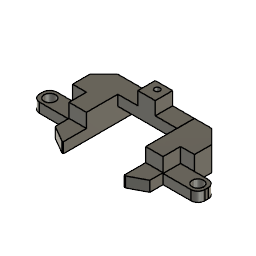
Frame (Autodesk Fusion 360 archive; units mm, degrees)
design "Static Arm"
Autodesk Fusion 360 part; units mm, degrees
(part 1 of 2)
sketch "Sketch1" plane through (0, 0, 0) normal (0, 0, 1) x (1, 0, 0)
  line L0 (2.54, 0) -> (57.7596, 0)
  line L1 (60.2996, 2.54) -> (60.2996, 3.81)
  line L2 (57.7596, 6.35) -> (2.54, 6.35)
  line L3 (0, 3.81) -> (0, 2.54)
  circle A0 centre (3.175, 3.175) radius 2.0955
  circle A1 centre (57.1246, 3.175) radius 2.0955
  arc A2 (60.2996, 3.81) -> (57.7596, 6.35) centre (57.7596, 3.81) ccw
  arc A3 (57.7596, 0) -> (60.2996, 2.54) centre (57.7596, 2.54) ccw
  arc A4 (2.54, 6.35) -> (0, 3.81) centre (2.54, 3.81) ccw
  arc A5 (0, 2.54) -> (2.54, 0) centre (2.54, 2.54) ccw
  line L4 (13.335, 17.78) -> (41.275, 17.78)
  line L5 (41.275, 17.78) -> (41.275, 11.43)
  line L6 (41.275, 11.43) -> (13.335, 11.43)
  line L7 (13.335, 11.43) -> (13.335, 17.78)
  line L8 (13.335, 17.78) -> (19.685, 17.78)
  line L9 (19.685, 17.78) -> (19.685, 0)
  line L10 (19.685, 0) -> (13.335, 0)
  line L11 (13.335, 0) -> (13.335, 17.78)
  line L12 (47.5996, 17.78) -> (41.2496, 17.78)
  line L13 (41.2496, 17.78) -> (41.2496, 0)
  line L14 (41.2496, 0) -> (47.5996, 0)
  line L15 (47.5996, 0) -> (47.5996, 17.78)
  line L16 (13.335, 17.78) -> (8.255, 17.78)
  line L17 (8.255, 17.78) -> (8.255, 0)
  line L18 (8.255, 0) -> (13.335, 0)
  line L19 (13.335, 0) -> (13.335, 17.78)
  line L20 (13.335, 17.78) -> (8.255, 12.7)
  line L21 (47.5996, 17.78) -> (52.6796, 17.78)
  line L22 (52.6796, 17.78) -> (52.6796, 0)
  line L23 (52.6796, 0) -> (47.5996, 0)
  line L24 (47.5996, 0) -> (47.5996, 17.78)
  line L25 (47.5996, 17.78) -> (52.6796, 12.7)
  point P0 (60.2996, 0)
  dimension "d1" = 6.35
  dimension "d2" = 60.2996
  dimension "d3" = 4.191
  dimension "d4" = 4.191
  dimension "d5" = 53.9496
  dimension "d6" = 3.175
  dimension "d7" = 3.175
  dimension "d8" = 2.54
  dimension "d9" = 2.54
  dimension "d10" = 2.54
  dimension "d11" = 2.54
  dimension "d14" = 6.35
  dimension "d15" = 10.16
  dimension "d17" = 6.35
  dimension "d18" = 10.16
  dimension "d19" = 5.08
  dimension "d20" = 6.35
  dimension "d39" = 27.94
  dimension "d80" = 5.08
  dimension "d81" = 45
  dimension "d82" = 5.08
  dimension "d83" = 45
  constraint horizontal L0
  constraint vertical L1
  constraint horizontal L2
  constraint vertical L3
  constraint horizontal A0.centre A1.centre
  constraint tangent L2 A2
  constraint tangent L1 A2
  constraint coincident P0 L0
  constraint coincident P0 L1
  constraint tangent L0 A3
  constraint tangent L1 A3
  constraint tangent L3 A4
  constraint tangent L2 A4
  constraint coincident origin L3
  constraint coincident origin L0
  constraint tangent L3 A5
  constraint tangent L0 A5
  constraint horizontal L4
  constraint vertical L5
  constraint horizontal L6
  constraint vertical L7
  constraint horizontal L8
  constraint vertical L9
  constraint horizontal L10
  constraint vertical L11
  constraint coincident L0 L9.end
  constraint horizontal L12
  constraint vertical L13
  constraint horizontal L14
  constraint vertical L15
  constraint coincident L0 L13.end
  constraint coincident L4 L12.start
  constraint horizontal L16
  constraint vertical L17
  constraint horizontal L18
  constraint vertical L19
  constraint coincident L0 L17.end
  constraint coincident L17 L20.end
  constraint horizontal L21
  constraint vertical L22
  constraint horizontal L23
  constraint vertical L24
  constraint coincident L0 L22.end
  constraint coincident L22 L25.end
  measures "d1" distance of L0 L2
  measures "d2" distance of origin P0
  measures "d3" diameter of A0
  measures "d4" diameter of A1
  measures "d5" distance of A0.centre A1.centre
  measures "d6" distance of L3 A0.centre
  measures "d7" vertical distance of origin A0.centre
  measures "d8" radius of A2
  measures "d9" radius of A3
  measures "d10" radius of A4
  measures "d11" radius of A5
  measures "d14" distance of L4 L6
  measures "d15" distance of A0.centre L11
  measures "d17" distance of L13 L15
  measures "d18" distance of A3.centre L15
  measures "d19" distance of L2 L6
  measures "d20" distance of L9 L11
  measures "d39" distance of L4.start L4.end
  measures "d80" distance of L4.start L16.end
  measures "d81" angle of L16 L20
  measures "d82" distance of L12.start L21.end
  measures "d83" angle of L21 L25
extrude "Extrude1" add sketch "Sketch1" along normal blind 3.81 contours L0 L2 L3 A4 A5 L17 | L0 L2 L11 L17 L18 L19 | L0 L2 L9 L10 L11 L19 | L2 L7 L11 L17 L19 L20 | L2 L6 L9 L11 L19 | L0 L2 L13 L14 L15 L24 | L4 L6 L7 L8 L9 L11 L19 | L0 L2 L15 L22 L23 L24 | L2 L5 L6 L12 L13 L15 L24 | L4 L6 L9 L13 | L0 L1 L2 A2 A3 L22 | L2 L15 L22 L24 L25 makes body 1
sketch "Sketch5" plane through (0, 0, 3.81) normal (0, 0, -1) x (1, 0, 0)
  circle A0 centre (63.4746, -3.175) radius 2.0955
  circle A1 centre (3.175, -3.175) radius 2.0955
  line L0 (47.5996, 0) -> (47.5996, -11.43)
  line L1 (47.5996, -11.43) -> (19.335, -11.43)
  line L2 (19.335, -11.43) -> (19.335, 0)
  line L3 (19.335, 0) -> (2.54, 0)
  arc A2 (2.54, 0) -> (0, -2.54) centre (2.54, -2.54) ccw
  line L4 (0, -2.54) -> (0, -3.81)
  arc A3 (0, -3.81) -> (2.54, -6.35) centre (2.54, -3.81) ccw
  line L5 (2.54, -6.35) -> (13.335, -6.35)
  line L6 (13.335, -6.35) -> (13.335, -17.78)
  line L7 (13.335, -17.78) -> (53.9496, -17.78)
  line L8 (53.9496, -17.78) -> (53.9496, -6.35)
  line L9 (53.9496, -6.35) -> (64.1096, -6.35)
  arc A4 (64.1096, -6.35) -> (66.6496, -3.81) centre (64.1096, -3.81) ccw
  line L10 (66.6496, -3.81) -> (66.6496, -2.54)
  arc A5 (66.6496, -2.54) -> (64.1096, 0) centre (64.1096, -2.54) ccw
  line L11 (64.1096, 0) -> (47.5996, 0)
  line L12 (26.9748, -11.43) -> (33.3248, -11.43)
  line L13 (33.3248, -11.43) -> (33.3248, -17.78)
  line L14 (33.3248, -17.78) -> (26.9748, -17.78)
  line L15 (26.9748, -17.78) -> (26.9748, -11.43)
  circle A6 centre (3.175, -3.175) radius 2.0955
  line L16 (8.255, -6.35) -> (2.54, -6.35)
  arc A7 (0, -3.81) -> (2.54, -6.35) centre (2.54, -3.81) ccw
  line L17 (0, -3.81) -> (0, -2.54)
  arc A8 (2.54, 0) -> (0, -2.54) centre (2.54, -2.54) ccw
  line L18 (2.54, 0) -> (19.685, 0)
  line L19 (19.685, 0) -> (19.685, -11.43)
  line L20 (19.685, -11.43) -> (41.2496, -11.43)
  line L21 (41.2496, -11.43) -> (41.2496, -17.78)
  line L22 (41.2496, -17.78) -> (13.335, -17.78)
  line L23 (13.335, -17.78) -> (8.255, -12.7)
  line L24 (8.255, -12.7) -> (8.255, -6.35)
  dimension "d35" = 6.35
  dimension "d36" = 26.9748
  constraint horizontal L12
  constraint vertical L13
  constraint horizontal L14
  constraint vertical L15
  constraint coincident L7 L13.end
  constraint coincident L1 L12.start
  measures "d35" distance of L13 L15
  measures "d36" distance of origin L15
extrude "Extrude4" add sketch "Sketch5" against normal blind 4.8006 contours L1 L7 L12 L13 L14 L15 L20 L22 bodies 1
sketch "Sketch2" plane through (0, 0, 8.6106) normal (0, 0, -1) x (1, 0, 0)
  circle A0 centre (63.4746, -3.175) radius 2.0955
  circle A1 centre (3.175, -3.175) radius 2.0955
  line L0 (47.5996, 0) -> (47.5996, -11.43)
  line L1 (47.5996, -11.43) -> (36.4998, -11.43)
  line L2 (19.335, -11.43) -> (19.335, 0)
  line L3 (19.335, 0) -> (2.54, 0)
  arc A2 (2.54, 0) -> (0, -2.54) centre (2.54, -2.54) ccw
  line L4 (0, -2.54) -> (0, -3.81)
  arc A3 (0, -3.81) -> (2.54, -6.35) centre (2.54, -3.81) ccw
  line L5 (2.54, -6.35) -> (13.335, -6.35)
  line L6 (13.335, -6.35) -> (13.335, -17.78)
  line L7 (36.4998, -17.78) -> (53.9496, -17.78)
  line L8 (53.9496, -17.78) -> (53.9496, -6.35)
  line L9 (53.9496, -6.35) -> (64.1096, -6.35)
  arc A4 (64.1096, -6.35) -> (66.6496, -3.81) centre (64.1096, -3.81) ccw
  line L10 (66.6496, -3.81) -> (66.6496, -2.54)
  arc A5 (66.6496, -2.54) -> (64.1096, 0) centre (64.1096, -2.54) ccw
  line L11 (64.1096, 0) -> (47.5996, 0)
  circle A6 centre (30.1498, -15.3416) radius 1
  line L12 (36.4998, -11.43) -> (36.4998, -17.78)
  line L13 (30.1498, -17.78) -> (30.1498, -11.43)
  line L14 (30.1498, -11.43) -> (19.335, -11.43)
  line L15 (13.335, -17.78) -> (30.1498, -17.78)
  line L16 (30.1498, -17.78) -> (36.4998, -17.78)
  line L17 (36.4998, -17.78) -> (36.4998, -11.43)
  line L18 (36.4998, -11.43) -> (30.1498, -11.43)
  line L19 (30.1498, -11.43) -> (30.1498, -17.78)
  circle A7 centre (63.4746, -3.175) radius 2.0955
  circle A8 centre (3.175, -3.175) radius 2.0955
  line L20 (47.5996, -11.43) -> (47.5996, 0)
  line L21 (2.54, 0) -> (19.335, 0)
  arc A9 (66.6496, -2.54) -> (64.1096, 0) centre (64.1096, -2.54) ccw
  line L22 (66.6496, -2.54) -> (66.6496, -3.81)
  arc A10 (64.1096, -6.35) -> (66.6496, -3.81) centre (64.1096, -3.81) ccw
  line L23 (13.335, -6.35) -> (2.54, -6.35)
  line L24 (53.9496, -6.35) -> (53.9496, -17.78)
  line L25 (30.1498, -17.78) -> (13.335, -17.78)
  line L26 (13.335, -17.78) -> (13.335, -6.35)
  arc A11 (0, -3.81) -> (2.54, -6.35) centre (2.54, -3.81) ccw
  line L27 (0, -3.81) -> (0, -2.54)
  arc A12 (2.54, 0) -> (0, -2.54) centre (2.54, -2.54) ccw
  line L28 (19.335, 0) -> (19.335, -11.43)
  line L29 (19.335, -11.43) -> (30.1498, -11.43)
  line L30 (30.1498, -11.43) -> (30.1498, -17.78)
  line L31 (36.4998, -17.78) -> (36.4998, -11.43)
  line L32 (36.4998, -11.43) -> (47.5996, -11.43)
  line L33 (47.5996, 0) -> (64.1096, 0)
  line L34 (64.1096, -6.35) -> (53.9496, -6.35)
  line L35 (53.9496, -17.78) -> (36.4998, -17.78)
  line L36 (33.3248, -17.78) -> (26.9748, -17.78)
  line L37 (26.9748, -17.78) -> (26.9748, -11.43)
  line L38 (26.9748, -11.43) -> (33.3248, -11.43)
  line L39 (33.3248, -11.43) -> (33.3248, -17.78)
  dimension "d21" = 2
  dimension "d24" = 3.9116
  dimension "d53" = 30.1498
  measures "d21" diameter of A6
  measures "d24" distance of L1 A6.centre
  measures "d53" distance of L4 A6.centre
extrude "Extrude2" cut sketch "Sketch2" along normal blind 12.7 contours A6 L13 L19 L30 | A6 L13 L19 L30 bodies 1
sketch "Sketch3" plane through (0, 0, 3.81) normal (0, 0, 1) x (-1, 0, 0)
  line L0 (-41.2496, 0) -> (-57.7596, 0)
  line L1 (-57.7596, -6.35) -> (-52.6796, -6.35)
  line L2 (-41.275, -11.43) -> (-41.2496, -11.43)
  circle A0 centre (-16.51, -14.605) radius 2.1
  circle A1 centre (-44.4246, -14.605) radius 2.1
  line L3 (-47.5996, -17.78) -> (-41.275, -17.78)
  line L4 (-41.275, -17.78) -> (-41.275, -11.43)
  line L5 (-41.2496, -11.43) -> (-41.2496, 0)
  arc A2 (-57.7596, 0) -> (-60.2996, -2.54) centre (-57.7596, -2.54) ccw
  line L6 (-60.2996, -2.54) -> (-60.2996, -3.81)
  arc A3 (-60.2996, -3.81) -> (-57.7596, -6.35) centre (-57.7596, -3.81) ccw
  circle A4 centre (-57.1246, -3.175) radius 2.0955
  line L7 (-52.6796, -6.35) -> (-52.6796, -12.7)
  line L8 (-52.6796, -12.7) -> (-47.5996, -17.78)
  dimension "d27" = 4.2
  dimension "d28" = 4.2
  dimension "d40" = 14.605
  dimension "d41" = 16.51
  dimension "d42" = 27.9146
  constraint horizontal A0.centre A1.centre
  measures "d27" diameter of A1
  measures "d28" diameter of A0
  measures "d40" vertical distance of origin A0.centre
  measures "d41" horizontal distance of origin A0.centre
  measures "d42" distance of A0.centre A1.centre
sketch "Sketch6" plane through (0, 0, 0) normal (0, 0, -1) x (1, 0, 0)
  circle A0 centre (57.1246, -3.175) radius 2.0955
  line L0 (52.6796, -6.35) -> (57.7596, -6.35)
  arc A1 (57.7596, -6.35) -> (60.2996, -3.81) centre (57.7596, -3.81) ccw
  line L1 (60.2996, -3.81) -> (60.2996, -2.54)
  arc A2 (60.2996, -2.54) -> (57.7596, 0) centre (57.7596, -2.54) ccw
  line L2 (57.7596, 0) -> (41.2496, 0)
  line L3 (41.2496, 0) -> (41.2496, -11.43)
  line L4 (41.2496, -11.43) -> (41.275, -11.43)
  line L5 (41.275, -11.43) -> (41.275, -17.78)
  line L6 (41.275, -17.78) -> (47.5996, -17.78)
  line L7 (41.2496, 0) -> (47.5996, 0)
  line L8 (47.5996, 0) -> (47.5996, -17.78)
  line L9 (47.5996, -17.78) -> (41.2496, -17.78)
  line L10 (41.2496, -17.78) -> (41.2496, 0)
  line L11 (47.5996, 0) -> (57.7596, 0)
  line L12 (60.2996, -2.54) -> (60.2996, -3.81)
  line L13 (57.7596, -6.35) -> (47.5996, -6.35)
  line L14 (47.5996, -6.35) -> (47.5996, 0)
  arc A3 (60.2996, -2.54) -> (57.7596, 0) centre (57.7596, -2.54) ccw
  arc A4 (57.7596, -6.35) -> (60.2996, -3.81) centre (57.7596, -3.81) ccw
  line L15 (19.685, -17.78) -> (13.335, -17.78)
  line L16 (13.335, -17.78) -> (13.335, 0)
  line L17 (13.335, 0) -> (19.685, 0)
  line L18 (19.685, 0) -> (19.685, -17.78)
  line L19 (13.335, 0) -> (2.54, 0)
  line L20 (0, -2.54) -> (0, -3.81)
  line L21 (2.54, -6.35) -> (13.335, -6.35)
  line L22 (13.335, -6.35) -> (13.335, 0)
  arc A5 (2.54, 0) -> (0, -2.54) centre (2.54, -2.54) ccw
  arc A6 (0, -3.81) -> (2.54, -6.35) centre (2.54, -3.81) ccw
  circle A7 centre (3.175, -3.175) radius 2.0955
  circle A8 centre (16.51, -14.5999) radius 2.0955
  line L23 (47.5996, -17.78) -> (52.6796, -12.7)
  line L24 (52.6796, -12.7) -> (52.6796, -6.35)
  point P0 (19.685, 0)
  point P1 (0, -2.54)
  point P2 (41.2496, -17.78)
  point P3 (13.335, -17.78)
  dimension "d43" = 2.54
  dimension "d44" = 2.54
  dimension "d45" = 10.16
  dimension "d46" = 1.27
  dimension "d54" = 6.35
  dimension "d55" = 2.54
  dimension "d56" = 2.54
  dimension "d57" = 6.35
  dimension "d58" = 3.175
  dimension "d59" = 4.191
  dimension "d60" = 3.175
  dimension "d61" = 4.191
  dimension "d62" = 3.1801
  dimension "d63" = 3.175
  constraint horizontal L7
  constraint vertical L8
  constraint horizontal L9
  constraint vertical L10
  constraint coincident L6.end L8.end
  constraint coincident L2.end L3.start
  constraint horizontal L11
  constraint vertical L12
  constraint horizontal L13
  constraint vertical L14
  constraint tangent L11 A3
  constraint tangent L12 A3
  constraint tangent L12 A4
  constraint tangent L13 A4
  constraint horizontal L15
  constraint vertical L16
  constraint horizontal L17
  constraint vertical L18
  constraint coincident P0 L17.end
  constraint horizontal L19
  constraint vertical L20
  constraint horizontal L21
  constraint vertical L22
  constraint tangent L20 A5
  constraint tangent L19 A5
  constraint tangent L20 A6
  constraint tangent L21 A6
  constraint coincident P1 L20.start
  measures "d43" radius of A3
  measures "d44" radius of A4
  measures "d45" distance of L13.end L0.end
  measures "d46" distance of L1.end A1.end
  measures "d54" distance of L16 L18
  measures "d55" radius of A5
  measures "d56" radius of A6
  measures "d57" distance of L19 L21
  measures "d58" distance of L19 A7.centre
  measures "d59" diameter of A7
  measures "d60" distance of L20 A7.centre
  measures "d61" diameter of A8
  measures "d62" distance of L15 A8.centre
  measures "d63" distance of L16 A8.centre
extrude "Extrude6" cut sketch "Sketch6" against normal blind 7.62 contours L0 A1 L1 A2 L2 L8 L11 L12 L13 L14 A3 A4 | L16 L19 L20 L21 L22 A5 A6 bodies 1
extrude "Extrude5" add sketch "Sketch6" along normal blind 5.08 separate body contours L0 A1 L1 A2 L2 L8 L11 L12 L13 L14 A3 A4 | L2 L3 L4 L5 L6 L7 L8 L9 L10 L14 | L15 L16 L17 L18 L22 | L16 L19 L20 L21 L22 A5 A6 | A8 makes body 2 at (43.3747, 5.9267, 0) makes body 3 at (17.5683, 8.0433, 0)
extrude "Extrude7" cut sketch "Sketch6" along normal blind 1.27 contours L0 A1 L1 A2 L2 L8 L11 L12 L13 L14 A3 A4 | L16 L19 L20 L21 L22 A5 A6 bodies 2
extrude "Extrude8" cut sketch "Sketch6" along normal blind 1.27 contours L16 L19 L20 L21 L22 A5 A6 bodies 3
sketch "Sketch7" plane through (0, 0, 0) normal (0, -1, 0) x (1, 0, 0)
  line L0 (13.335, -1.27) -> (2.54, -1.27)
  line L1 (2.54, -1.27) -> (2.54, -5.08)
  line L2 (2.54, -5.08) -> (19.685, -5.08)
  line L3 (19.685, -5.08) -> (19.685, 0)
  line L4 (19.685, 0) -> (13.335, 0)
  line L5 (13.335, 0) -> (13.335, -1.27)
  line L6 (13.335, -1.27) -> (19.685, -1.27)
  line L7 (19.685, -1.27) -> (19.685, -5.08)
  line L8 (19.685, -5.08) -> (13.335, -5.08)
  line L9 (13.335, -5.08) -> (13.335, -1.27)
  dimension "d66" = 6.35
  constraint horizontal L6
  constraint vertical L7
  constraint horizontal L8
  constraint vertical L9
  constraint coincident L2 L3.start
  constraint coincident L0 L5.end
  constraint coincident L2.end L3.start
  measures "d66" distance of L7 L9
extrude "Extrude9" add sketch "Sketch7" along normal blind 8.4226 contours L2 L3 L6 L7 L8 L9 bodies 3
chamfer "Chamfer1" distance 5.842 angle 30.099 1 edges at (13.335, -8.4226, -3.175) measured on face at (15.4517, -8.4226, -3.81) on bodies 3
sketch "Sketch8" plane through (0, 0, 0) normal (0, -1, 0) x (1, 0, 0)
  line L0 (57.7596, -1.27) -> (47.5996, -1.27)
  line L1 (47.5996, -1.27) -> (47.5996, 0)
  line L2 (47.5996, 0) -> (41.2496, 0)
  line L3 (41.2496, 0) -> (41.2496, -5.08)
  line L4 (41.2496, -5.08) -> (57.7596, -5.08)
  line L5 (57.7596, -5.08) -> (57.7596, -1.27)
  line L6 (41.2496, -5.08) -> (47.5996, -5.08)
  line L7 (47.5996, -5.08) -> (47.5996, -1.27)
  line L8 (47.5996, -1.27) -> (41.2496, -1.27)
  line L9 (41.2496, -1.27) -> (41.2496, -5.08)
  constraint horizontal L6
  constraint vertical L7
  constraint horizontal L8
  constraint vertical L9
  constraint coincident L0.end L1.start
  constraint coincident L3.end L4.start
extrude "Extrude10" add sketch "Sketch8" along normal blind 7.874 contours L3 L4 L6 L7 L8 L9 bodies 2
chamfer "Chamfer2" distance 5.842 angle 27.549 1 edges at (47.5996, -7.874, -3.175) measured on face at (45.4829, -7.874, -3.81) on bodies 2
sketch "Sketch9" plane through (0, 0, 0) normal (0, 0, -1) x (1, 0, 0)
  line L0 (47.5996, -6.35) -> (47.5996, 0)
  line L1 (47.5996, 0) -> (41.2496, 0)
  line L2 (41.2496, 0) -> (41.2496, -11.43)
  line L3 (41.2496, -11.43) -> (41.275, -11.43)
  line L4 (41.275, -11.43) -> (41.275, -17.78)
  line L5 (41.275, -17.78) -> (47.5996, -17.78)
  line L6 (47.5996, -17.78) -> (52.6796, -12.7)
  line L7 (52.6796, -12.7) -> (52.6796, -6.35)
  line L8 (52.6796, -6.35) -> (47.5996, -6.35)
  line L9 (47.5996, -6.35) -> (52.6796, -6.35)
  line L10 (52.6796, -6.35) -> (52.6796, -12.7)
  line L11 (52.6796, -12.7) -> (47.5996, -12.7)
  line L12 (47.5996, -12.7) -> (47.5996, -6.35)
  line L13 (47.5996, -12.7) -> (47.5996, -17.78)
  line L14 (52.6796, -12.7) -> (47.5996, -17.78)
  constraint horizontal L9
  constraint vertical L10
  constraint horizontal L11
  constraint vertical L12
  constraint coincident L6.end L7.start
  constraint coincident L0.start L8.end
  constraint coincident L5.end L6.start
extrude "Extrude11" add sketch "Sketch9" along normal blind 5.08 contours L7 L8 L9 L10 L11 L12 | L6 L11 L13 L14 bodies 1 3 2
sketch "Sketch10" plane through (0, 0, 0) normal (0, 0, -1) x (1, 0, 0)
  line L0 (13.335, 0) -> (13.335, -6.35)
  line L1 (13.335, -6.35) -> (8.255, -6.35)
  line L2 (8.255, -6.35) -> (8.255, -12.7)
  line L3 (8.255, -12.7) -> (13.335, -17.78)
  line L4 (13.335, -17.78) -> (41.2496, -17.78)
  line L5 (41.2496, -17.78) -> (41.2496, -11.43)
  line L6 (41.2496, -11.43) -> (19.685, -11.43)
  line L7 (19.685, -11.43) -> (19.685, 0)
  line L8 (19.685, 0) -> (13.335, 0)
  circle A0 centre (30.1498, -15.3416) radius 1
  line L9 (8.255, -6.35) -> (13.335, -6.35)
  line L10 (13.335, -6.35) -> (13.335, -12.7)
  line L11 (13.335, -12.7) -> (8.255, -12.7)
  line L12 (8.255, -12.7) -> (8.255, -6.35)
  line L13 (13.335, -12.7) -> (13.335, -17.78)
  line L14 (8.255, -12.7) -> (13.335, -17.78)
  dimension "d86" = 5.08
  constraint horizontal L9
  constraint vertical L10
  constraint horizontal L11
  constraint vertical L12
  constraint coincident L1.end L2.start
  constraint coincident L2.end L3.start
  constraint coincident L3.end L4.start
  measures "d86" distance of L10.end L2.end
extrude "Extrude12" add sketch "Sketch10" along normal blind 5.08 contours L1 L2 L9 L10 L11 L12 | L3 L11 L13 L14 bodies 1 3
sketch "Sketch11" plane through (0, 0, -1.27) normal (0, 0, 1) x (-1, 0, 0)
  circle A0 centre (-3.175, -3.175) radius 2.0955
  arc A1 (-2.54, -6.35) -> (0, -3.81) centre (-2.54, -3.81) ccw
  line L0 (0, -3.81) -> (0, -2.54)
  arc A2 (0, -2.54) -> (-2.54, 0) centre (-2.54, -2.54) ccw
  line L1 (-2.54, 0) -> (-13.335, 0)
  line L2 (-13.335, 0) -> (-13.335, -6.35)
  line L3 (-13.335, -6.35) -> (-8.255, -6.35)
  line L4 (-8.255, -6.35) -> (-2.54, -6.35)
  line L5 (-13.335, -6.35) -> (5.715, -6.35)
  line L6 (5.715, -6.35) -> (5.715, 6.35)
  line L7 (5.715, 6.35) -> (-13.335, 6.35)
  line L8 (-13.335, 6.35) -> (-13.335, -6.35)
  line L9 (-47.5996, -6.35) -> (-66.6496, -6.35)
  line L10 (-66.6496, -6.35) -> (-66.6496, 6.35)
  line L11 (-66.6496, 6.35) -> (-47.5996, 6.35)
  line L12 (-47.5996, 6.35) -> (-47.5996, -6.35)
  point P0 (-47.5996, -6.35)
  dimension "d89" = 12.7
  dimension "d90" = 19.05
  dimension "d91" = 12.7
  dimension "d92" = 19.05
  constraint horizontal L5
  constraint vertical L6
  constraint horizontal L7
  constraint vertical L8
  constraint coincident L2.end L3.start
  constraint horizontal L9
  constraint vertical L10
  constraint horizontal L11
  constraint vertical L12
  constraint coincident P0 L9.start
  measures "d89" distance of L9.end L10.end
  measures "d90" distance of P0 L9.end
  measures "d91" distance of L5.end L6.end
  measures "d92" distance of L2.end L5.end
extrude "Extrude13" cut sketch "Sketch11" against normal blind 0.254 bodies 1
fillet "Fillet1" [rolled back] radius 10.16
fillet "Fillet2" [rolled back] radius 10.16
equation "d5 = 2.374 in - 0.25 in"
equation "d36 = ( 2.624 / 2 ) * 1 in - 0.25 in"
equation "d42 = 1.349 in - 0.25 in"
equation "d53 = ( 2.374 / 2 ) * 1 in"

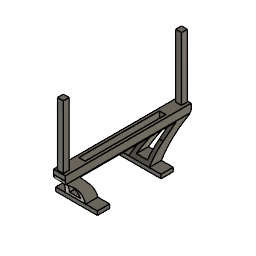
design "Rear Top Mount"
Autodesk Fusion 360 part; units mm, degrees
sketch "Sketch1" plane through (0, 0, 0) normal (0, 1, 0) x (1, 0, 0)
  line L0 (0, 0) -> (-25.4, 0)
  line L1 (-25.4, 0) -> (-25.4, -3.175)
  line L2 (-25.4, -3.175) -> (0, -3.175)
  line L3 (0, -3.175) -> (0, 0)
  line L4 (-25.4, 0) -> (-33.655, 0)
  line L5 (-33.655, 0) -> (-33.655, -3.175)
  line L6 (-33.655, -3.175) -> (-25.4, -3.175)
  line L7 (-25.4, -3.175) -> (-25.4, 0)
  line L8 (-26.035, -3.175) -> (-15.24, -28.575)
  line L9 (-15.24, -28.575) -> (-5.715, -28.575)
  line L10 (-5.715, -28.575) -> (-9.525, -3.175)
  line L11 (-15.24, -28.575) -> (-5.715, -28.575)
  line L12 (-5.715, -28.575) -> (-5.715, -34.925)
  line L13 (-5.715, -34.925) -> (-15.24, -34.925)
  line L14 (-15.24, -34.925) -> (-15.24, -28.575)
  dimension "d3" = 33.655
  dimension "d4" = 8.255
  dimension "d5" = 25.4
  dimension "d6" = 3.175
  dimension "d7" = 3.175
  dimension "d26" = 6.35
  dimension "d27" = 25.4
  dimension "d28" = 9.525
  dimension "d30" = 16.51
  dimension "d31" = 3.81
  dimension "d32" = 9.525
  constraint horizontal L0
  constraint vertical L1
  constraint horizontal L2
  constraint vertical L3
  constraint coincident L0.start L3.end
  constraint horizontal L4
  constraint vertical L5
  constraint horizontal L6
  constraint vertical L7
  constraint coincident L2 L8.start
  constraint perpendicular L1 L9
  constraint coincident L2 L10.end
  constraint horizontal L11
  constraint vertical L12
  constraint horizontal L13
  constraint vertical L14
  constraint horizontal L0.end L4.end
  measures "d3" distance of L3 L5
  measures "d4" distance of L0.end L4.end
  measures "d5" distance of L0.start L0.end
  measures "d6" distance of L4.end L5.end
  measures "d7" distance of L0.start L2.end
  measures "d26" distance of L9.end L12.end
  measures "d27" distance of L2 L9
  measures "d28" distance of L12 L14
  measures "d30" distance of L8.start L10.end
  measures "d31" horizontal distance of L10.end L9.end
  measures "d32" distance of L2.end L10.end
extrude "Extrude1" add sketch "Sketch1" along normal blind 30.1625 makes body 1
sketch "Sketch2" plane through (0, 0, 3.175) normal (0, 0, 1) x (-1, 0, 0)
  line L0 (33.655, 0) -> (26.035, 0)
  line L1 (0, 0) -> (0, -30.1625)
  line L2 (26.035, -30.1625) -> (33.655, -30.1625)
  line L3 (33.655, -30.1625) -> (33.655, 0)
  circle A0 centre (28.8925, -25.4) radius 2.1971
  circle A1 centre (3.4925, -25.4) radius 2.1971
  line L4 (26.035, 0) -> (26.035, -30.1625)
  line L5 (9.525, 0) -> (0, 0)
  line L6 (0, -30.1625) -> (9.525, -30.1625)
  line L7 (9.525, -30.1625) -> (9.525, 0)
  dimension "d10" = 4.3942
  dimension "d11" = 4.3942
  dimension "d12" = 4.7625
  dimension "d13" = 4.7625
  dimension "d14" = 25.4
  dimension "d15" = 4.7625
  measures "d10" diameter of A0
  measures "d11" diameter of A1
  measures "d12" distance of L2 A0.centre
  measures "d13" distance of L2 A1.centre
  measures "d14" distance of A0.centre A1.centre
  measures "d15" distance of L3 A0.centre
sketch "Sketch5" plane through (0, 0, 34.925) normal (0, 0, 1) x (-1, 0, 0)
  line L0 (15.24, 0) -> (5.715, 0)
  line L1 (5.715, 0) -> (5.715, -30.1625)
  line L2 (5.715, -30.1625) -> (15.24, -30.1625)
  line L3 (15.24, -30.1625) -> (15.24, 0)
  line L4 (12.8588, -29.3688) -> (8.0962, -29.3688)
  line L5 (8.0962, -29.3688) -> (8.0962, -24.6063)
  line L6 (8.0962, -24.6063) -> (12.8588, -24.6063)
  line L7 (12.8588, -24.6063) -> (12.8588, -29.3688)
  dimension "d33" = 4.7625
  dimension "d34" = 4.7625
  dimension "d35" = 0.7937
  dimension "d36" = 2.3813
  constraint horizontal L4
  constraint vertical L5
  constraint horizontal L6
  constraint vertical L7
  measures "d33" distance of L4.end L5.end
  measures "d34" distance of L4.start L4.end
  measures "d35" distance of L2 L4
  measures "d36" distance of L1 L5
extrude "Extrude5" add sketch "Sketch5" along normal blind 50.8 contours L4 L5 L6 L7 bodies 1
sketch "Sketch6" plane through (0, 0, 0) normal (0, -1, 0) x (1, 0, 0)
  line L0 (-9.525, 3.175) -> (-5.715, 28.575)
  line L1 (-5.715, 28.575) -> (-5.715, 34.925)
  line L2 (-5.715, 34.925) -> (-15.24, 34.925)
  line L3 (-15.24, 34.925) -> (-15.24, 28.575)
  line L4 (-15.24, 28.575) -> (-26.035, 3.175)
  line L5 (-26.035, 3.175) -> (-33.655, 3.175)
  line L6 (-33.655, 3.175) -> (-33.655, 0)
  line L7 (-33.655, 0) -> (0, 0)
  line L8 (0, 0) -> (0, 3.175)
  line L9 (0, 3.175) -> (-9.525, 3.175)
  line L10 (-21.2358, 6.35) -> (-12.2593, 6.35)
  line L11 (-12.2593, 6.35) -> (-8.9255, 28.575)
  line L12 (-8.9255, 28.575) -> (-11.7902, 28.575)
  line L13 (-11.7902, 28.575) -> (-21.2358, 6.35)
  line L14 (-13.9069, 23.5944) -> (-10.3578, 28.575)
  line L15 (-10.3578, 28.575) -> (-9.0638, 27.6529)
  dimension "d39" = 6.35
  dimension "d40" = 6.35
  dimension "d41" = 3.175
  dimension "d42" = 3.175
  dimension "d43" = 90
  dimension "d44" = 6.1157
  constraint horizontal L10
  constraint parallel L10 L12
  constraint parallel L4 L13
  constraint coincident L10.start L13.end
  constraint parallel L0 L11
  constraint coincident L13 L14.start
  constraint midpoint L12 L14.end
  constraint coincident L11 L15.end
  measures "d39" distance of L7 L10
  measures "d40" distance of L2 L12
  measures "d41" distance of L0 L11
  measures "d42" distance of L4 L13
  measures "d43" angle of L14 L15
  measures "d44" distance of L14.start L14.end
extrude "Extrude6" cut sketch "Sketch6" against normal blind 30.48 contours L10 L11 L13 L14 L15 bodies 1
sketch "Sketch7" plane through (-33.655, 0, 0) normal (-1, 0, 0) x (0, -1, 0)
  line L0 (0, 0) -> (0, 3.175)
  line L1 (0, 3.175) -> (-30.1625, 3.175)
  line L2 (-30.1625, 3.175) -> (-30.1625, 0)
  line L3 (-30.1625, 0) -> (0, 0)
  line L4 (-30.1625, 0) -> (-23.1775, 0)
  line L5 (-23.1775, 0) -> (-23.1775, 28.575)
  line L6 (-23.1775, 28.575) -> (-30.1625, 28.575)
  line L7 (-30.1625, 28.575) -> (-30.1625, 0)
  arc A0 (-9.9568, 3.175) -> (-28.0506, 27.1338) centre (-57.7318, -14.0932) ccw
  arc A1 (0, 3.175) -> (-13.236, 22.0663) centre (-43.3882, -13.142) ccw
  arc A2 (-20.6375, 34.925) -> (-13.236, 22.0663) centre (1.2205, 38.947) ccw
  line L8 (0, 3.175) -> (0, 28.575)
  line L9 (0, 34.925) -> (-30.1625, 34.925)
  line L10 (-20.6375, 34.925) -> (-30.1625, 34.925)
  line L11 (-30.1625, 31.2565) -> (-30.1625, 34.925)
  arc A3 (-30.1625, 31.2565) -> (-28.0506, 27.1338) centre (-25.0825, 31.2565) ccw
  line L12 (-9.9568, 3.175) -> (-9.9568, 0)
  line L13 (0, 0) -> (-9.9568, 0)
  line L14 (-30.1625, 34.925) -> (0, 34.925)
  line L15 (0, 34.925) -> (0, 0)
  line L16 (0, 0) -> (-30.1625, 0)
  line L17 (-30.1625, 0) -> (-30.1625, 34.925)
  line L18 (-18.0414, 27.8598) -> (-9.1332, 18.089)
  line L19 (-18.0414, 27.8598) -> (-18.0414, 34.925)
  line L20 (-24.5261, 34.925) -> (-20.6375, 34.925)
  dimension "d47" = 28.575
  dimension "d48" = 6.985
  dimension "d50" = 9.9568
  dimension "d51" = 5.08
  dimension "d70" = 22.225
  dimension "d71" = 46.355
  dimension "d72" = 9.525
  dimension "d73" = 50.8
  constraint horizontal L4
  constraint vertical L5
  constraint horizontal L6
  constraint vertical L7
  constraint coincident L2.end L3.start
  constraint coincident L1 A0.start
  constraint coincident L0.end L1.start
  constraint coincident L5.end A1
  constraint tangent A1 A2
  constraint coincident A2.start L9
  constraint coincident L9.end L10.end
  constraint coincident L6.end L11
  constraint coincident L6.end A0
  constraint tangent L11 A3
  constraint tangent A0 A3
  constraint coincident L3 L12.end
  constraint perpendicular L3 L12
  constraint coincident L0.start L3.end
  constraint horizontal L14
  constraint vertical L15
  constraint horizontal L16
  constraint vertical L17
  constraint coincident L9 A2.start
  constraint coincident A2.start L10.start
  constraint midpoint A2 L18.start
  constraint coincident A1 L18.end
  constraint tangent A1 L18
  constraint coincident L14 L19.end
  constraint perpendicular L14 L19
  constraint coincident L9 L20.start
  measures "d47" distance of L2.end L6.end
  measures "d48" distance of L2.end L4.end
  measures "d50" distance of A0.start L0.end
  measures "d51" radius of A3
  measures "d70" radius of A2
  measures "d71" radius of A1
  measures "d72" distance of A2.start L9.end
  measures "d73" radius of A0
extrude "Extrude7" cut sketch "Sketch7" against normal blind 33.655 contours A1 L8 L9 L14 L15 L18 L19 | L1 L3 L5 L12 L16 | L1 L5 A0 | L1 L2 L3 L4 L5 L7 L16 L17 | L1 L5 L6 L7 A0 A3 L17 | L6 A3 L17 bodies 1
ref_plane "WorkPlane1" through (0, -20.6375, 0) normal (0, 1, 0) x (0, 0, 1)
mirror "Mirror1" about plane through (0, -20.6375, 0) normal (0, 1, 0) of bodies 1 makes body 2
extrude "Extrude10" add 1 faces at (-10.4376, 18.0414, 32.8083) along direction (0, -1, 0) blind 81.28 on bodies 1 bodies 1 2
sketch "Sketch10" plane through (0, 0, 34.925) normal (0, 0, 1) x (-1, 0, 0)
  line L0 (12.8588, 70.6437) -> (12.8588, 65.8813)
  line L1 (12.8588, 65.8813) -> (8.0962, 65.8813)
  line L2 (8.0962, 65.8813) -> (8.0962, 70.6437)
  line L3 (8.0962, 70.6437) -> (12.8588, 70.6437)
  line L4 (5.715, 71.4375) -> (5.715, -30.1625)
  line L5 (5.715, -30.1625) -> (15.24, -30.1625)
  line L6 (15.24, -30.1625) -> (15.24, 71.4375)
  line L7 (15.24, 71.4375) -> (5.715, 71.4375)
  line L8 (12.8588, -24.6063) -> (12.8588, -29.3688)
  line L9 (12.8588, -29.3688) -> (8.0962, -29.3688)
  line L10 (8.0962, -29.3688) -> (8.0962, -24.6063)
  line L11 (8.0962, -24.6063) -> (12.8588, -24.6063)
  line L12 (8.001, 53.1813) -> (13.081, 53.1813)
  line L13 (13.081, 53.1813) -> (13.081, -11.9062)
  line L14 (8.001, -11.9063) -> (8.001, 53.1813)
  line L15 (13.081, -11.9063) -> (8.001, -11.9063)
  dimension "d76" = 5.08
  dimension "d77" = 2.286
  dimension "d78" = 12.7
  dimension "d80" = 12.7
  constraint horizontal L12
  constraint vertical L13
  constraint vertical L14
  constraint perpendicular L14 L15
  measures "d76" distance of L13 L14
  measures "d77" distance of L4 L14
  measures "d78" distance of L1 L12
  measures "d80" distance of L11 L15
extrude "Extrude11" cut sketch "Sketch10" against normal blind 6.4262 contours L12 L13 L14 L15 bodies 1
equation "d3 = 1.375 in - 0.05 in"
equation "d4 = 0.375 in - 0.05 in"
equation "d8 = 1.5 in - 0.3125 in"
equation "d12 = ( 0.375 / 2 ) * 1 in"
equation "d13 = ( 3 / 16 ) * 1 in"
equation "d15 = ( 3 / 16 ) * 1 in"
equation "d28 = ( 3 / 8 ) * 1 in"
equation "d33 = ( 3 / 16 ) * 1 in"
equation "d34 = ( 3 / 16 ) * 1 in"
equation "d35 = ( 1 / 32 ) * 1 in"
equation "d36 = ( 3 / 32 ) * 1 in"
equation "d65 = -0.415 in - 0.3975 in"

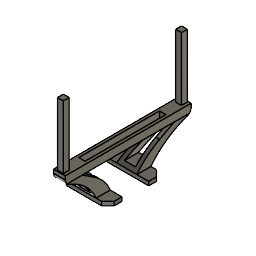
design "Front Top Mount"
Autodesk Fusion 360 part; units mm, degrees
sketch "Sketch1" plane through (0, 0, 0) normal (0, 1, 0) x (1, 0, 0)
  line L0 (0, 0) -> (-25.4, 0)
  line L1 (-25.4, 0) -> (-25.4, -3.175)
  line L2 (-25.4, -3.175) -> (0, -3.175)
  line L3 (0, -3.175) -> (0, 0)
  line L4 (-25.4, 0) -> (-33.655, 0)
  line L5 (-33.655, 0) -> (-33.655, -3.175)
  line L6 (-33.655, -3.175) -> (-25.4, -3.175)
  line L7 (-25.4, -3.175) -> (-25.4, 0)
  line L8 (-26.035, -3.175) -> (-15.24, -28.575)
  line L9 (-15.24, -28.575) -> (-5.715, -28.575)
  line L10 (-5.715, -28.575) -> (-9.525, -3.175)
  line L11 (-15.24, -28.575) -> (-5.715, -28.575)
  line L12 (-5.715, -28.575) -> (-5.715, -34.925)
  line L13 (-5.715, -34.925) -> (-15.24, -34.925)
  line L14 (-15.24, -34.925) -> (-15.24, -28.575)
  dimension "d3" = 33.655
  dimension "d4" = 8.255
  dimension "d5" = 25.4
  dimension "d6" = 3.175
  dimension "d7" = 3.175
  dimension "d26" = 6.35
  dimension "d27" = 25.4
  dimension "d28" = 9.525
  dimension "d30" = 16.51
  dimension "d31" = 3.81
  dimension "d32" = 9.525
  constraint horizontal L0
  constraint vertical L1
  constraint horizontal L2
  constraint vertical L3
  constraint coincident L0.start L3.end
  constraint horizontal L4
  constraint vertical L5
  constraint horizontal L6
  constraint vertical L7
  constraint coincident L2 L8.start
  constraint perpendicular L1 L9
  constraint coincident L2 L10.end
  constraint horizontal L11
  constraint vertical L12
  constraint horizontal L13
  constraint vertical L14
  constraint horizontal L0.end L4.end
  measures "d3" distance of L3 L5
  measures "d4" distance of L0.end L4.end
  measures "d5" distance of L0.start L0.end
  measures "d6" distance of L4.end L5.end
  measures "d7" distance of L0.start L2.end
  measures "d26" distance of L9.end L12.end
  measures "d27" distance of L2 L9
  measures "d28" distance of L12 L14
  measures "d30" distance of L8.start L10.end
  measures "d31" horizontal distance of L10.end L9.end
  measures "d32" distance of L2.end L10.end
extrude "Extrude1" add sketch "Sketch1" along normal blind 40.0558 makes body 1
sketch "Sketch2" plane through (0, 0, 3.175) normal (0, 0, 1) x (-1, 0, 0)
  line L0 (33.655, 0) -> (26.035, 0)
  line L1 (0, 0) -> (0, -40.0558)
  line L2 (26.035, -40.0558) -> (33.655, -40.0558)
  line L3 (33.655, -40.0558) -> (33.655, 0)
  circle A0 centre (28.8925, -35.2933) radius 2.1971
  circle A1 centre (3.4925, -35.2933) radius 2.1971
  line L4 (26.035, 0) -> (26.035, -40.0558)
  line L5 (9.525, 0) -> (0, 0)
  line L6 (0, -40.0558) -> (9.525, -40.0558)
  line L7 (9.525, -40.0558) -> (9.525, 0)
  dimension "d10" = 4.3942
  dimension "d11" = 4.3942
  dimension "d12" = 4.7625
  dimension "d13" = 4.7625
  dimension "d14" = 25.4
  dimension "d15" = 4.7625
  measures "d10" diameter of A0
  measures "d11" diameter of A1
  measures "d12" distance of L2 A0.centre
  measures "d13" distance of L2 A1.centre
  measures "d14" distance of A0.centre A1.centre
  measures "d15" distance of L3 A0.centre
sketch "Sketch5" plane through (0, 0, 34.925) normal (0, 0, 1) x (-1, 0, 0)
  line L0 (15.24, 0) -> (5.715, 0)
  line L1 (5.715, 0) -> (5.715, -40.0558)
  line L2 (5.715, -40.0558) -> (15.24, -40.0558)
  line L3 (15.24, -40.0558) -> (15.24, 0)
  line L4 (12.8588, -39.2621) -> (8.0962, -39.2621)
  line L5 (8.0962, -39.2621) -> (8.0962, -34.4996)
  line L6 (8.0962, -34.4995) -> (12.8588, -34.4995)
  line L7 (12.8588, -34.4995) -> (12.8588, -39.262)
  dimension "d33" = 4.7625
  dimension "d34" = 4.7625
  dimension "d35" = 0.7937
  dimension "d36" = 2.3813
  constraint horizontal L4
  constraint vertical L5
  constraint horizontal L6
  constraint vertical L7
  measures "d33" distance of L4.end L6.start
  measures "d34" distance of L4.start L4.end
  measures "d35" distance of L2 L4
  measures "d36" distance of L1 L5
extrude "Extrude5" add sketch "Sketch5" along normal blind 50.8 contours L4 L5 L6 L7 bodies 1
sketch "Sketch6" plane through (0, 0, 0) normal (0, -1, 0) x (1, 0, 0)
  line L0 (-9.525, 3.175) -> (-5.715, 28.575)
  line L1 (-5.715, 28.575) -> (-5.715, 34.925)
  line L2 (-5.715, 34.925) -> (-15.24, 34.925)
  line L3 (-15.24, 34.925) -> (-15.24, 28.575)
  line L4 (-15.24, 28.575) -> (-26.035, 3.175)
  line L5 (-26.035, 3.175) -> (-33.655, 3.175)
  line L6 (-33.655, 3.175) -> (-33.655, 0)
  line L7 (-33.655, 0) -> (0, 0)
  line L8 (0, 0) -> (0, 3.175)
  line L9 (0, 3.175) -> (-9.525, 3.175)
  line L10 (-21.2358, 6.35) -> (-12.2593, 6.35)
  line L11 (-12.2593, 6.35) -> (-8.9255, 28.575)
  line L12 (-8.9255, 28.575) -> (-11.7902, 28.575)
  line L13 (-11.7902, 28.575) -> (-21.2358, 6.35)
  line L14 (-13.9069, 23.5944) -> (-10.3578, 28.575)
  line L15 (-10.3578, 28.575) -> (-9.0638, 27.6529)
  dimension "d39" = 6.35
  dimension "d40" = 6.35
  dimension "d41" = 3.175
  dimension "d42" = 3.175
  dimension "d43" = 90
  dimension "d44" = 6.1157
  constraint horizontal L10
  constraint parallel L10 L12
  constraint parallel L4 L13
  constraint coincident L10.start L13.end
  constraint parallel L0 L11
  constraint coincident L13 L14.start
  constraint midpoint L12 L14.end
  constraint coincident L11 L15.end
  measures "d39" distance of L7 L10
  measures "d40" distance of L2 L12
  measures "d41" distance of L0 L11
  measures "d42" distance of L4 L13
  measures "d43" angle of L14 L15
  measures "d44" distance of L14.start L14.end
extrude "Extrude6" cut sketch "Sketch6" against normal blind 30.48 contours L10 L11 L13 L14 L15 bodies 1
sketch "Sketch7" plane through (-33.655, 0, 0) normal (-1, 0, 0) x (0, -1, 0)
  line L0 (0, 0) -> (0, 3.175)
  line L1 (0, 3.175) -> (-40.0558, 3.175)
  line L2 (-40.0558, 3.175) -> (-40.0558, 0)
  line L3 (-40.0558, 0) -> (0, 0)
  line L4 (-40.0558, 0) -> (-33.0708, 0)
  line L5 (-33.0708, 0) -> (-33.0708, 28.575)
  line L6 (-33.0708, 28.575) -> (-40.0558, 28.575)
  line L7 (-40.0558, 28.575) -> (-40.0558, 0)
  arc A0 (-11.43, 3.175) -> (-36.9758, 27.3729) centre (-56.9758, -19.3244) ccw
  arc A1 (0, 3.175) -> (-20.4363, 24.2029) centre (-41.7539, -16.9595) ccw
  arc A2 (-30.5308, 34.925) -> (-20.4363, 24.2029) centre (-10.2155, 43.9384) ccw
  line L8 (0, 3.175) -> (0, 28.575)
  line L9 (0, 34.925) -> (-40.0558, 34.925)
  line L10 (-30.5308, 34.925) -> (-40.0558, 34.925)
  line L11 (-40.0558, 32.0426) -> (-40.0558, 34.925)
  arc A3 (-40.0558, 32.0426) -> (-36.9758, 27.3729) centre (-34.9758, 32.0426) ccw
  line L12 (-11.43, 3.175) -> (-11.43, 0)
  line L13 (0, 0) -> (-11.43, 0)
  line L14 (-40.0558, 34.925) -> (0, 34.925)
  line L15 (0, 34.925) -> (0, 0)
  line L16 (0, 0) -> (-40.0558, 0)
  line L17 (-40.0558, 0) -> (-40.0558, 34.925)
  line L18 (-26.3974, 28.7036) -> (-15.5702, 21.2923)
  line L19 (-26.3974, 28.7036) -> (-26.3974, 34.925)
  line L20 (-24.5261, 34.925) -> (-30.5308, 34.925)
  dimension "d47" = 28.575
  dimension "d48" = 6.985
  dimension "d50" = 11.43
  dimension "d51" = 5.08
  dimension "d70" = 22.225
  dimension "d71" = 46.355
  dimension "d72" = 9.525
  dimension "d73" = 50.8
  constraint horizontal L4
  constraint vertical L5
  constraint horizontal L6
  constraint vertical L7
  constraint coincident L2.end L3.start
  constraint coincident L1 A0.start
  constraint coincident L0.end L1.start
  constraint coincident L5.end A1
  constraint tangent A1 A2
  constraint coincident A2.start L9
  constraint coincident L9.end L10.end
  constraint coincident L6.end L11
  constraint coincident L6.end A0
  constraint tangent L11 A3
  constraint tangent A0 A3
  constraint coincident L3 L12.end
  constraint perpendicular L3 L12
  constraint coincident L0.start L3.end
  constraint horizontal L14
  constraint vertical L15
  constraint horizontal L16
  constraint vertical L17
  constraint coincident L9 A2.start
  constraint coincident A2.start L10.start
  constraint midpoint A2 L18.start
  constraint coincident A1 L18.end
  constraint tangent A1 L18
  constraint coincident L14 L19.end
  constraint perpendicular L14 L19
  constraint coincident L9 L20.start
  measures "d47" distance of L2.end L6.end
  measures "d48" distance of L2.end L4.end
  measures "d50" distance of A0.start L0.end
  measures "d51" radius of A3
  measures "d70" radius of A2
  measures "d71" radius of A1
  measures "d72" distance of A2.start L9.end
  measures "d73" radius of A0
extrude "Extrude7" cut sketch "Sketch7" against normal blind 33.655 contours A1 L8 L9 L14 L15 L18 L19 L20 | L1 L3 L5 L12 L16 | L1 L5 A0 | L1 L2 L3 L4 L5 L7 L16 L17 | L1 L5 L6 L7 A0 A3 L17 | L6 A3 L17 bodies 1
sketch "Sketch8" plane through (0, 0, 3.175) normal (0, 0, 1) x (-1, 0, 0)
  line L0 (9.525, 0) -> (0, 0)
  line L1 (0, 0) -> (0, -11.43)
  line L2 (9.525, -11.43) -> (9.525, 0)
  line L3 (0, -11.43) -> (9.525, -11.43)
  line L4 (5.08, -11.43) -> (0, -6.35)
  dimension "d68" = 45
  dimension "d69" = 5.08
  constraint coincident L3 L4.start
  constraint coincident L1 L4.end
  measures "d68" angle of L3 L4
  measures "d69" distance of L1.end L4.end
extrude "Extrude8" cut sketch "Sketch8" against normal blind 3.175 contours L1 L3 L4 bodies 1
ref_plane "WorkPlane1" through (0, -10.7442, 0) normal (0, 1, 0) x (0, 0, 1)
mirror "Mirror1" about plane through (0, -10.7442, 0) normal (0, 1, 0) of bodies 1 makes body 2
extrude "Extrude10" add 1 faces at (-12.065, 26.3974, 30.7774) along direction (0, -1, 0) blind 78.74 on bodies 1 bodies 1 2
sketch "Sketch10" plane through (0, 0, 34.925) normal (0, 0, 1) x (-1, 0, 0)
  line L0 (12.8588, 60.7504) -> (12.8588, 55.9879)
  line L1 (12.8588, 55.9879) -> (8.0962, 55.9879)
  line L2 (8.0962, 55.9879) -> (8.0962, 60.7504)
  line L3 (8.0962, 60.7504) -> (12.8588, 60.7504)
  line L4 (5.715, 61.5442) -> (5.715, -40.0558)
  line L5 (5.715, -40.0558) -> (15.24, -40.0558)
  line L6 (15.24, -40.0558) -> (15.24, 61.5442)
  line L7 (15.24, 61.5442) -> (5.715, 61.5442)
  line L8 (12.8588, -34.4995) -> (12.8588, -39.262)
  line L9 (12.8588, -39.2621) -> (8.0962, -39.2621)
  line L10 (8.0962, -39.2621) -> (8.0962, -34.4996)
  line L11 (8.0962, -34.4995) -> (12.8588, -34.4995)
  line L12 (8.001, 43.2879) -> (13.081, 43.2879)
  line L13 (13.081, 43.2879) -> (13.081, -21.7995)
  line L14 (8.001, -21.7995) -> (8.001, 43.2879)
  line L15 (13.081, -21.7995) -> (8.001, -21.7995)
  dimension "d76" = 5.08
  dimension "d77" = 2.286
  dimension "d78" = 12.7
  dimension "d80" = 12.7
  constraint horizontal L12
  constraint vertical L13
  constraint vertical L14
  constraint perpendicular L14 L15
  measures "d76" distance of L13 L14
  measures "d77" distance of L4 L14
  measures "d78" distance of L1 L12
  measures "d80" distance of L11 L15
extrude "Extrude11" cut sketch "Sketch10" against normal blind 6.4262 contours L12 L13 L14 L15 bodies 1
equation "d3 = 1.375 in - 0.05 in"
equation "d4 = 0.375 in - 0.05 in"
equation "d8 = 1.5 in + 0.077 in"
equation "d12 = ( 0.375 / 2 ) * 1 in"
equation "d13 = ( 3 / 16 ) * 1 in"
equation "d15 = ( 3 / 16 ) * 1 in"
equation "d28 = ( 3 / 8 ) * 1 in"
equation "d33 = ( 3 / 16 ) * 1 in"
equation "d34 = ( 3 / 16 ) * 1 in"
equation "d35 = ( 1 / 32 ) * 1 in"
equation "d36 = ( 3 / 32 ) * 1 in"

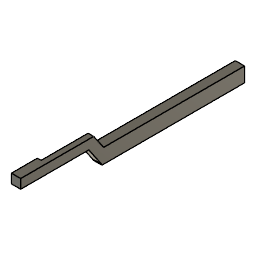
design "Left Cross Base Beam"
Autodesk Fusion 360 part; units mm, degrees
sketch "Sketch1" plane through (0, 0, 0) normal (1, 0, 0) x (0, 1, 0)
  circle A0 centre (0, 0) radius 2.1971
  circle A1 centre (25.4, 0) radius 2.1971
  line L0 (10.16, 2.54) -> (15.24, 2.54)
  line L1 (15.24, 2.54) -> (15.24, -2.54)
  line L2 (15.24, -2.54) -> (10.16, -2.54)
  line L3 (10.16, -2.54) -> (10.16, 2.54)
  line L4 (-6.35, 4.7625) -> (31.75, 4.7625)
  line L5 (31.75, 4.7625) -> (31.75, -4.7625)
  line L6 (31.75, -4.7625) -> (-6.35, -4.7625)
  line L7 (-6.35, -4.7625) -> (-6.35, 4.7625)
  dimension "d1" = 25.4
  dimension "d2" = 4.3942
  dimension "d3" = 4.3942
  dimension "d4" = 5.08
  dimension "d5" = 5.08
  dimension "d6" = 2.54
  dimension "d7" = 10.16
  dimension "d8" = 9.525
  dimension "d9" = 38.1
  dimension "d10" = 4.7625
  dimension "d11" = 6.35
  constraint horizontal A0.centre A1.centre
  constraint horizontal L0
  constraint vertical L1
  constraint horizontal L2
  constraint vertical L3
  constraint coincident A0.centre origin
  constraint horizontal L4
  constraint vertical L5
  constraint horizontal L6
  constraint vertical L7
  measures "d1" distance of A0.centre A1.centre
  measures "d2" diameter of A0
  measures "d3" diameter of A1
  measures "d4" distance of L0.start L0.end
  measures "d5" distance of L0.start L2.end
  measures "d6" distance of A0.centre L0
  measures "d7" horizontal distance of A0.centre L2.end
  measures "d8" distance of L4.start L6.end
  measures "d9" distance of L4.start L4.end
  measures "d10" distance of A0.centre L4
  measures "d11" distance of A0.centre L7
extrude "Extrude1" add sketch "Sketch1" along normal blind 2.54 contours A0 | A1 | L0 L1 L2 L3 | L4 L5 L6 L7
sketch "Sketch2" plane through (2.54, 0, 0) normal (1, 0, 0) x (0, 1, 0)
  line L0 (-6.35, -4.7625) -> (31.75, -4.7625)
  line L1 (31.75, -4.7625) -> (31.75, 4.7625)
  line L2 (31.75, 4.7625) -> (-6.35, 4.7625)
  line L3 (-6.35, 4.7625) -> (-6.35, -4.7625)
  line L4 (31.75, 4.7625) -> (-6.35, 4.7625)
  line L5 (-6.35, 4.7625) -> (-6.35, -4.7625)
  line L6 (-6.35, -4.7625) -> (31.75, -4.7625)
  line L7 (31.75, -4.7625) -> (31.75, 4.7625)
  circle A0 centre (0, 0) radius 2.1971
  circle A1 centre (25.4, 0) radius 2.1971
  dimension "d14" = 4.3942
  dimension "d15" = 4.3942
  constraint horizontal L4
  constraint vertical L5
  constraint horizontal L6
  constraint vertical L7
  constraint coincident L0.start L3.end
  constraint coincident L1.end L2.start
  measures "d14" diameter of A0
  measures "d15" diameter of A1
extrude "Extrude2" add sketch "Sketch2" along normal blind 3.81 contours L0 L1 L2 L3 L4 L5 L6 L7 | A0 | A1
sketch "Sketch3" plane through (0, -6.35, 0) normal (0, -1, 0) x (1, 0, 0)
  line L0 (0, 4.7625) -> (0, -4.7625)
  line L1 (0, -4.7625) -> (6.35, -4.7625)
  line L2 (6.35, -4.7625) -> (6.35, 4.7625)
  line L3 (6.35, 4.7625) -> (0, 4.7625)
  line L4 (0, 4.7625) -> (6.35, 4.7625)
  line L5 (6.35, 4.7625) -> (6.35, -4.7625)
  line L6 (6.35, -4.7625) -> (0, -4.7625)
  line L7 (0, -4.7625) -> (0, 4.7625)
  constraint horizontal L4
  constraint vertical L5
  constraint horizontal L6
  constraint vertical L7
  constraint coincident L1.end L2.start
  constraint coincident L0.start L3.end
extrude "Extrude3" add sketch "Sketch3" along normal blind 127
sketch "Sketch4" plane through (6.35, 0, 0) normal (1, 0, 0) x (0, 1, 0)
  line L0 (31.75, -4.7625) -> (31.75, 4.7625)
  line L1 (31.75, 4.7625) -> (-133.35, 4.7625)
  line L2 (-133.35, 4.7625) -> (-133.35, -4.7625)
  line L3 (-133.35, -4.7625) -> (31.75, -4.7625)
  circle A0 centre (-47.625, 1.5875) radius 1.6
  circle A1 centre (-22.225, 1.5875) radius 1.6
  dimension "d22" = 3.2
  dimension "d23" = 3.2
  dimension "d27" = 6.35
  dimension "d62" = 25.4
  constraint horizontal A0.centre A1.centre
  measures "d22" diameter of A0
  measures "d23" diameter of A1
  measures "d27" distance of L3 A1.centre
  measures "d62" distance of A0.centre A1.centre
sketch "Sketch6" plane through (0, -133.35, 0) normal (0, -1, 0) x (1, 0, 0)
  line L0 (0, -4.7625) -> (6.35, -4.7625)
  line L1 (6.35, -4.7625) -> (6.35, 4.7625)
  line L2 (6.35, 4.7625) -> (0, 4.7625)
  line L3 (0, 4.7625) -> (0, -4.7625)
  line L4 (0, 4.7625) -> (6.35, 4.7625)
  line L5 (6.35, 4.7625) -> (6.35, -1.5875)
  line L6 (6.35, -1.5875) -> (0, -1.5875)
  line L7 (0, -1.5875) -> (0, 4.7625)
  dimension "d29" = 6.35
  dimension "d30" = 6.35
  constraint horizontal L4
  constraint vertical L5
  constraint horizontal L6
  constraint vertical L7
  constraint coincident L2.end L3.start
  measures "d29" distance of L2.end L1.end
  measures "d30" distance of L2.end L6.end
extrude "Extrude5" cut sketch "Sketch6" against normal blind 67.945 contours L0 L1 L3 L6
sketch "Sketch7" plane through (0, 0, 0) normal (-1, 0, 0) x (0, -1, 0)
  line L0 (65.405, -4.7625) -> (65.405, -1.5875)
  line L1 (65.405, -1.5875) -> (133.35, -1.5875)
  line L2 (133.35, -1.5875) -> (133.35, 4.7625)
  line L3 (133.35, 4.7625) -> (-31.75, 4.7625)
  line L4 (-31.75, 4.7625) -> (-31.75, -4.7625)
  line L5 (-31.75, -4.7625) -> (65.405, -4.7625)
  circle A0 centre (117.475, 1.5875) radius 2.1
  dimension "d33" = 4.2
  dimension "d34" = 3.175
  dimension "d35" = 15.875
  measures "d33" diameter of A0
  measures "d34" distance of L3 A0.centre
  measures "d35" distance of L2 A0.centre
extrude "Extrude6" cut sketch "Sketch7" against normal blind 6.35 contours A0